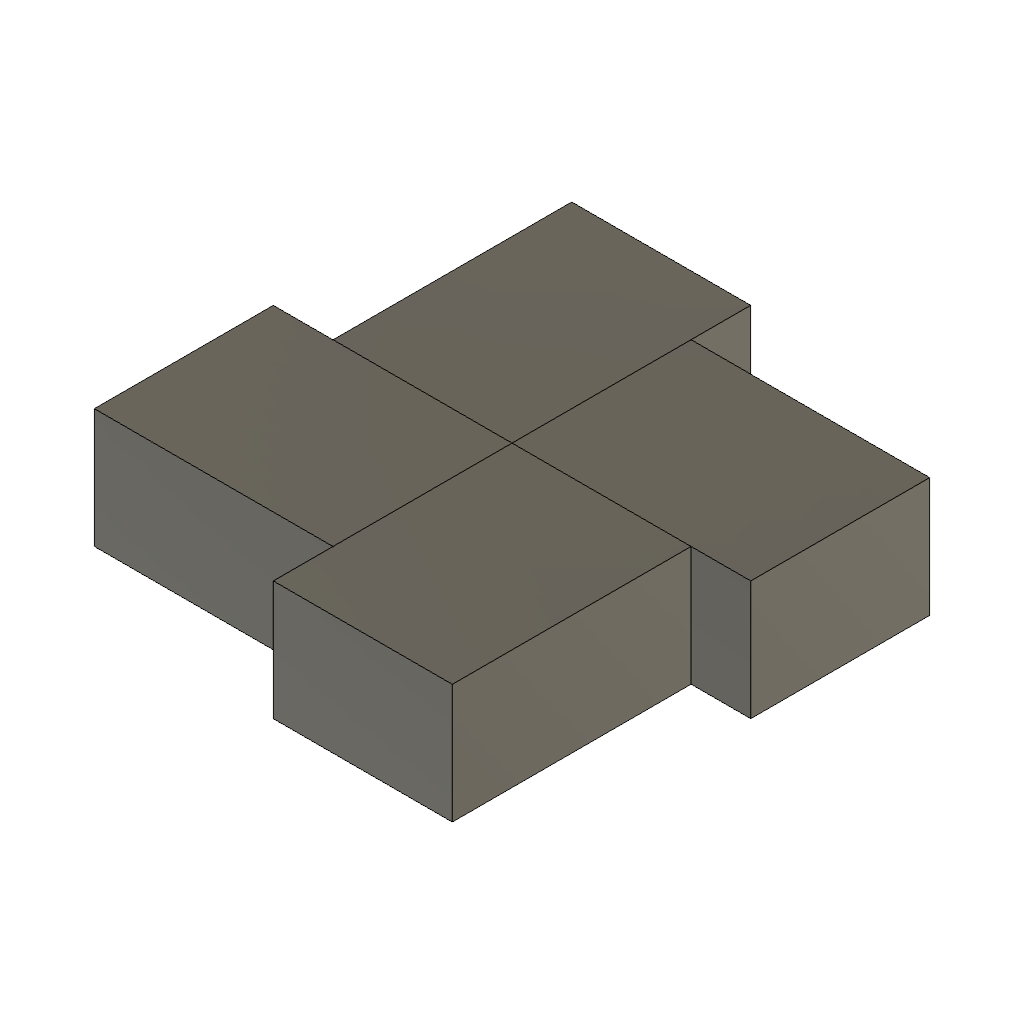
CircPattern (Autodesk Fusion 360 design; units mm, degrees)
part number: 2026-11-12-11-46-37-399
Autodesk Fusion 360 part; units mm, degrees
sketch "Base sketch" plane through (0, 0, 0) normal (0, 0, 1) x (1, 0, 0)
  line L0 (0, 0) -> (40, 0)
  line L1 (40, 0) -> (40, 30)
  line L2 (40, 30) -> (0, 30)
  line L3 (0, 30) -> (0, 0)
extrude "Base extrude" add sketch "Base sketch" along normal blind 20 makes body 1
pattern_circular "Body ring" count 4 over 360 about axis through (0, 0, 1.75) along (0, 0, 1) of bodies 1 makes body 2 at (-20, 13.3333, 0) makes body 3 at (-13.3333, -20, 0) makes body 4 at (20, -13.3333, 0)
